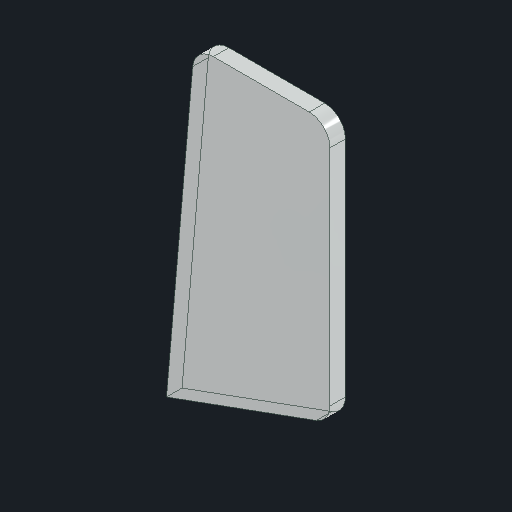
# Autodesk Inventor part: 7_6_2_vitre_conducteur
Saved by Autodesk Inventor 2026 (Build 300175000, 175)
## iProperties
Created: 2025-06-22
Part Number: 7_6_2_vitre_conducteur
Material: Glass
Document SubType Name: Modeling
Designer: remg9
Density: 2.18 g/cm^3
Appearance: Clear
Author: remg9
Autodesk Inventor part; units mm, degrees
ref_plane "YZ Plane" through (0, 0, 0) normal (1, 0, 0) x (0, 1, 0)
ref_plane "XZ Plane" through (0, 0, 0) normal (0, 1, 0) x (-1, 0, 0)
ref_plane "XY Plane" through (0, 0, 0) normal (0, 0, 1) x (1, 0, 0)
sketch "Sketch1" plane through (0, 0, 0) normal (0, 0, 1) x (1, 0, 0)
  line L0 (-18.5446, 4) -> (0, 4)
  line L1 (4, 0) -> (4, -43.1992)
  line L2 (1.3681, -46.9579) -> (-27.5903, -57.4979)
  line L3 (-27.5903, -57.4979) -> (-22.5293, 0.3486)
  arc A0 (-18.5446, 4) -> (-22.5293, 0.3486) centre (-18.5446, 0) ccw
  arc A1 (4, 0) -> (0, 4) centre (0, 0) ccw
  arc A2 (1.3681, -46.9579) -> (4, -43.1992) centre (0, -43.1992) ccw
  line L4 (4, -46) -> (4, 4) construction
  line L5 (4, 4) -> (-22.2099, 4) construction
  line L6 (-22.2099, 4) -> (-27.5903, -57.4979) construction
  line L7 (-27.5903, -57.4979) -> (4, -46) construction
  point P0 (-21.8031, 40.0355)
  dimension "d0" = 4
  dimension "d1" = 110
  dimension "d7" = 50
  dimension "d8" = 26.2099
  dimension "d9" = 61.4979
  dimension "d10" = 95
  constraints: 16 end point, 6 point on circle, 6 tangent, 4 collinear, 4 point on line, 3 centre point, 2 equal radius, 2 perpendicular, 1 coincident, 1 horizontal, 1 vertical
  measures "d0" radius of A0
  measures "d1" angle of L1 L2
  measures "d7" distance from line of L4.start L5
  measures "d8" distance of L4.end L5.end
  measures "d9" vertical distance of L5.end L6.end
  measures "d10" angle of L6 L0
extrude "Extrusion1" add sketch "Sketch1" along normal blind 3
body "Solid1"
